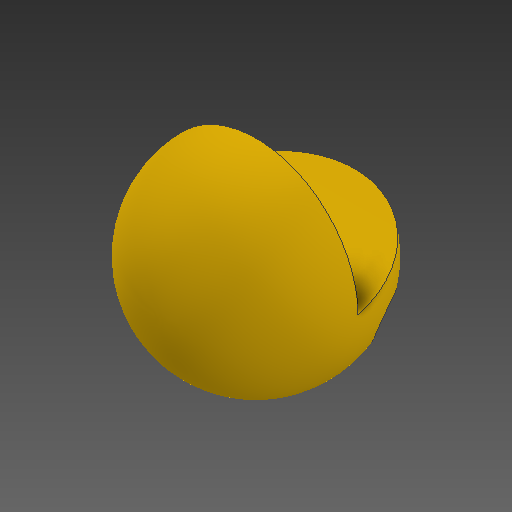
# Autodesk Inventor part: Pacman-friday21
Saved by Autodesk Inventor 2026.1 (Build 301233020, 233B)
## iProperties
Created: 2026-08-21
Part Number: Pacman-friday21
Material: Generic
Document SubType Name: Modeling
Designer: YmCris
Density: 1 g/cm^3
Appearance: Default
Author: YmCris
Autodesk Inventor part; units mm, degrees
ref_plane "XZ Plane" through (0, 0, 0) normal (0, 1, 0) x (-1, 0, 0)
ref_plane "XY Plane" through (0, 0, 0) normal (0, 0, 1) x (1, 0, 0)
sketch "Sketch1" plane through (0, 0, 0) normal (0, 0, 1) x (1, 0, 0)
  arc A0 (15.0101, 0) -> (-15.0101, 0) centre (0, 0) ccw
  line L0 (-15.0101, 0) -> (15.0101, 0)
  constraints: 2 end point, 2 point on circle, 1 centre point, 1 horizontal
revolve "Revolution1" add sketch "Sketch1" angle 285 about axis through (-15.0101, 0, 0) along (1, 0, 0)
ref_plane "Work Plane1" through (0, 0, 0) normal (1, 0, 0) x (0, 1, 0)
sketch "Sketch2" plane through (0, 0, 0) normal (1, 0, 0) x (0, 1, 0)
  circle A0 centre (-5.3704, -7.3061) radius 3
  point P0 (0, 0)
  dimension "d3" = 6
  constraints: 1 centre point
  measures "d3" diameter of A0
extrude "Extrusion1" cut sketch "Sketch2" along normal mid plane 28.5
body "Solid1"
